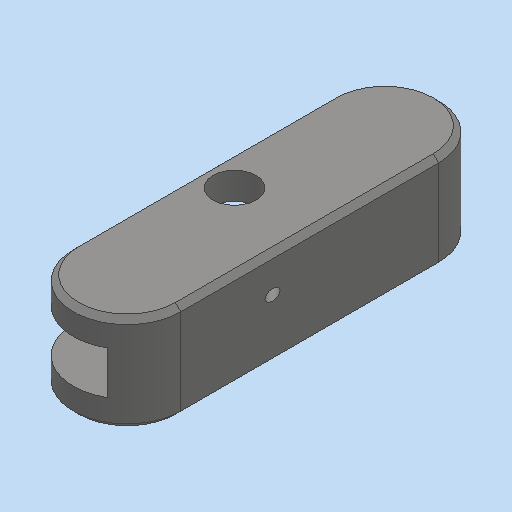
# Autodesk Inventor part: MM0948AN130_G01_109
Saved by Autodesk Inventor 2023.3 (Build 273359000, 359)
## iProperties
RuleStatus: InUse
Created: 2023-03-23
Part Number: MM0948AN130_G01_109
Material: 1.2379 X155CrVMo12-1
Description: =<RBPARTNOTITLE2>
Document SubType Name: Modeling
Designer: ric7an
Mass: 17.0391 g
Surface Area: 16.3762 cm^2
Volume: 2.17059 cm^3
Density: 7.85 g/cm^3
Appearance: Stahl - rostfrei AnP
AnP_Kategorie: 1
AnP_Material: =<Material>
MaxAbmaße: 9 x 34 x 10 (FM)
AnP_TemplVers: 20200821
RBDOCUMENTTYPE: DRF
RBDOCUMENTVERSION: 00
RBDRAWINGMAINSCALE: 1:1
RBDRAWINGMISSINGSPEC: --
RBDRAWINGVOLUME: --
RBDSV1: 0850
RBGBEDGESIN1: +0,5
RBGBEDGESIN2: +0,2
RBGBEDGESOUT1: -0,3
RBGBEDGESOUT2: -0,1
RBMATERIAL: =<Material>
RBMATMEETS: --
RBMATNO: =<Part Number>
RBPARTMADEOF: 9 x 34 x 10 (FM)
RBPARTNO: SIEHE MNR
RBPARTNOTITLE1: manufactured part
RBPARTNOTITLE2: Anfertigungsteil
RBPARTSAFETYINDICATOR: --
RBSURFACE: vaccum hardened 58 HRC ± 1
RBSURFACE2: vakuumgehaertet 58 HRC ± 1
RBZEDGESNORM: ISO13715:2002-06
RBZGENDIMCLASS: m
RBZGENDIMNORM: ISO 2768-1:1989-11
RBZGENGEOCLASS: H
RBZGENGEONORM: ISO 2768-2:1989-11
RBZSURFACENORM: ISO13D2:2002-02
RBZTOLERANCENORM: ISO 14405-1:2010-12
AnP_Kommentar_aktuell: =<Comments>
AnP_Material_aktuell: =<Material>
Author: FH/Wi
Keywords: =<RBPARTMADEOF>
Comments: =<RBSURFACE2>
Revision Number: 01
Autodesk Inventor part; units mm, degrees
ref_plane "XZ Plane" through (0, 0, 0) normal (0, 1, 0) x (-1, 0, 0)
ref_plane "XY Plane" through (0, 0, 0) normal (0, 0, 1) x (1, 0, 0)
sketch "Skizze1" plane through (0, 0, 0) normal (0, 0, 1) x (1, 0, 0)
  line L0 (0, 0) -> (0, 12) construction
  line L1 (5, 0) -> (5, 12)
  line L2 (-5, 12) -> (-5, 0)
  arc A0 (-5, 0) -> (5, 0) centre (0, 0) ccw
  arc A1 (5, 12) -> (-5, 12) centre (0, 12) ccw
  line L3 (0, 0) -> (0, -12) construction
  line L4 (-5, 0) -> (-5, -12)
  line L5 (5, -12) -> (5, 0)
  arc A2 (5, 0) -> (-5, 0) centre (0, 0) ccw
  arc A3 (-5, -12) -> (5, -12) centre (0, -12) ccw
  point P0 (0, 6)
  point P1 (0, -6)
  point P2 (-5, 0)
  point P3 (5, 0)
  dimension "d0" = 12
  dimension "d1" = 12
  dimension "d2" = 10
  dimension "d3" = 180
  constraints: 16 end point, 9 tangent, 8 point on circle, 4 centre point, 2 midpoint, 2 parallel, 1 vertical
  measures "d0" distance of L0.start L0.end
  measures "d1" distance of L0.start L3.end
  measures "d2" distance between parallel lines of L1 L2
  measures "d3" angle of L3 L0
extrude "Extrusion1" add sketch "Skizze1" along normal mid plane 9
sketch "Skizze2" plane through (-5, -12, -4.5) normal (-1, 0, 0) x (0, 0, 1)
  line L0 (2.5, 16.5) -> (6.5, 16.5)
  line L1 (6.5, 16.5) -> (6.5, -5)
  line L2 (6.5, -5) -> (2.5, -5)
  line L3 (2.5, -5) -> (2.5, 16.5)
  line L4 (0, -5) -> (9, -5) projected
  line L5 (4.5, 36.3) -> (4.5, -14.8) projected
  point P0 (4.5, 12)
  dimension "d6" = 4
  dimension "d7" = 21.5
  constraints: 8 end point, 2 parallel, 1 collinear, 1 horizontal, 1 perpendicular, 1 other
  measures "d6" distance of L0.start L0.end
  measures "d7" distance between parallel lines of L4 L0
extrude "Extrusion2" cut sketch "Skizze2" along normal blind 5 and the other way blind 7.5
sketch "Skizze3" plane through (0, 0, 4.5) normal (0, 0, 1) x (1, 0, 0)
  line L0 (0, 23.8) -> (0, -23.8) projected
  line L1 (-7, 0) -> (7, 0) projected
  point P0 (0, 0)
  point P1 (-2, 0)
  dimension "d38" = 2
  constraints: 1 point on line
  measures "d38" distance from line of L0 point (-2, 0)
hole "Bohrung1" at (-2, 0, 4.5) direction (0, 0, -1) diameter 4 end through all
fillet "Rundung1" radius 2 2 edges at (-1.25, 4.5, -2) (-1.25, 4.5, 2)
ref_plane "Arbeitsebene1" through (5, -12, 0) normal (0.7071, -0.7071, 0) x (0, 0, 1)
sketch "Skizze5" plane through (5, -12, 0) normal (0.7071, -0.7071, 0) x (0, 0, 1)
  line L0 (-4.5, -5.5355) -> (-4.5, -1.5355) projected
  point P0 (0, -4.9497)
  point P1 (1.1, -6.0355)
  dimension "d36" = 4.5
  dimension "d37" = 1.1
  measures "d36" vertical distance of L0.end point (1.1, -6.036)
  measures "d37" horizontal distance of point (0, -4.95) point (1.1, -6.036)
hole "Bohrung3" at (9.2678, -7.7322, 1.1) direction (-0.7071, 0.7071, 0) diameter 1 end through all
chamfer "Fase1" distance 0.5 angle 45 8 edges at (5, 0, 4.5) (0, 17, 4.5) (-5, 0, 4.5) (0, -17, 4.5) (0, -17, -4.5) (-5, 0, -4.5) (0, 17, -4.5) (5, 0, -4.5)
